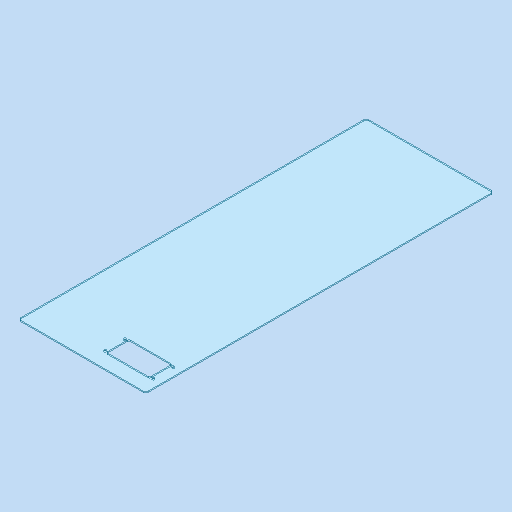
# Autodesk Inventor part: MM0948AN140_G01_106
Saved by Autodesk Inventor 2023.3 (Build 273359000, 359)
## iProperties
Part Number: MM0948AN140_G01_106
Material: Kst - PC (Eslon, klar)
Description: =<RBPARTNOTITLE2>
Document SubType Name: Modeling
Designer: ric7an
Mass: 1101.81 g
Surface Area: 6208.94 cm^2
Volume: 918.178 cm^3
Density: 1.2 g/cm^3
Appearance: Klar AnP
Created: 2023-03-23
RBDOCUMENTTYPE: DRF
RBDOCUMENTVERSION: 00
RBDRAWINGMAINSCALE: 1:1
RBDRAWINGMISSINGSPEC: --
RBDRAWINGVOLUME: --
RBGBEDGESIN1: +0,5
RBGBEDGESIN2: +0,2
RBGBEDGESOUT1: -0,3
RBGBEDGESOUT2: -0,1
RBMATERIAL: =<Material>
RBMATMEETS: --
RBMATNO: =<Part Number>
RBPARTMADEOF: 3 x 925 x 338,5 (FM)
RBPARTNO: SIEHE MNR
RBPARTNOTITLE1: manufactured part
RBPARTNOTITLE2: Anfertigungsteil
RBPARTSAFETYINDICATOR: --
RBSURFACE: --
RBSURFACE2: --
RBZEDGESNORM: ISO13715:2002-06
RBZGENDIMCLASS: m
RBZGENDIMNORM: ISO 2768-1:1989-11
RBZGENGEOCLASS: H
RBZGENGEONORM: ISO 2768-2:1989-11
RBZSURFACENORM: ISO13D2:2002-02
RBZTOLERANCENORM: ISO 14405-1:2010-12
AnP_Material: =<Material>
AnP_TemplVers: 20190222
AnP_Kategorie: 1
MaxAbmaße: 3 x 925 x 338,5 (FM)
AnP_Kommentar_aktuell: =<Comments>
AnP_Material_aktuell: =<Material>
Author: FH/Wi
Keywords: =<RBPARTMADEOF>
Comments: =<RBSURFACE2>
Revision Number: 01
Autodesk Inventor part; units mm, degrees
ref_plane "YZ Plane" through (0, 0, 0) normal (1, 0, 0) x (0, 1, 0)
ref_plane "XZ Plane" through (0, 0, 0) normal (0, 1, 0) x (-1, 0, 0)
ref_plane "XY Plane" through (0, 0, 0) normal (0, 0, 1) x (1, 0, 0)
sketch "Skizze1" plane through (0, 0, 0) normal (0, 0, 1) x (1, 0, 0)
  line L0 (-169.25, 462.5) -> (169.25, 462.5)
  line L1 (169.25, 462.5) -> (169.25, -462.5)
  line L2 (169.25, -462.5) -> (-169.25, -462.5)
  line L3 (-169.25, -462.5) -> (-169.25, 462.5)
  line L4 (0, 647.5) -> (0, -647.5) projected
  line L5 (-236.95, 0) -> (236.95, 0) projected
  point P0 (0, 0)
  dimension "d0" = 338.5
  dimension "d1" = 925
  constraints: 8 end point, 2 parallel, 1 horizontal, 1 perpendicular, 2 other
  measures "d0" distance of L0.start L0.end
  measures "d1" distance of L0.end L1.end
extrude "Extrusion1" add sketch "Skizze1" along normal blind 3
sketch "Skizze3" plane through (0, 0, 3) normal (0, 0, 1) x (1, 0, 0)
  line L0 (24.25, -362.5) -> (139.25, -362.5)
  line L1 (139.25, -362.5) -> (139.25, -422.5)
  line L2 (139.25, -422.5) -> (24.25, -422.5)
  line L3 (24.25, -422.5) -> (24.25, -362.5)
  line L4 (169.25, 462.5) -> (-169.25, 462.5) projected
  line L5 (169.25, -462.5) -> (169.25, 462.5) projected
  line L6 (-169.25, -462.5) -> (169.25, -462.5) projected
  point P0 (0, 0)
  dimension "d13" = 60
  dimension "d14" = 115
  dimension "d18" = 30
  dimension "d34" = 40
  constraints: 8 end point, 2 parallel, 1 horizontal, 1 perpendicular
  measures "d13" distance of L0.end L1.end
  measures "d14" distance of L0.start L0.end
  measures "d18" distance between parallel lines of L5 L1
  measures "d34" distance between parallel lines of L6 L2
extrude "Extrusion2" cut sketch "Skizze3" against normal through all
sketch "Skizze4" plane through (0, 0, 3) normal (0, 0, 1) x (1, 0, 0)
  line L0 (24.25, -362.5) -> (139.25, -362.5) projected
  line L1 (24.25, -422.5) -> (24.25, -362.5) projected
  point P0 (0, 0)
  point P1 (17.75, -366)
  point P2 (145.75, -366)
  point P3 (145.75, -419)
  point P4 (17.75, -419)
  dimension "d19" = 53
  dimension "d20" = 128
  dimension "d21" = 3.5
  dimension "d22" = 6.5
  constraints: 2 horizontal alignment, 2 vertical alignment
  measures "d19" distance of point (145.75, -419) point (145.75, -366)
  measures "d20" distance of point (145.75, -366) point (17.75, -366)
  measures "d21" distance from line of L0 point (145.75, -366)
  measures "d22" distance from line of L1 point (17.75, -366)
hole "Bohrung2" at (17.75, -366, 3) at (145.75, -366, 3) at (145.75, -419, 3) at (17.75, -419, 3) direction (0, 0, -1) diameter 5.5 end through all
fillet "Rundung1" radius 4 4 edges at (24.25, -362.5, 1.5) (24.25, -422.5, 1.5) (139.25, -362.5, 1.5) (139.25, -422.5, 1.5)
chamfer "Fase1" distance 6 angle 45 4 edges at (-169.25, -462.5, 1.5) (169.25, -462.5, 1.5) (169.25, 462.5, 1.5) (-169.25, 462.5, 1.5)
